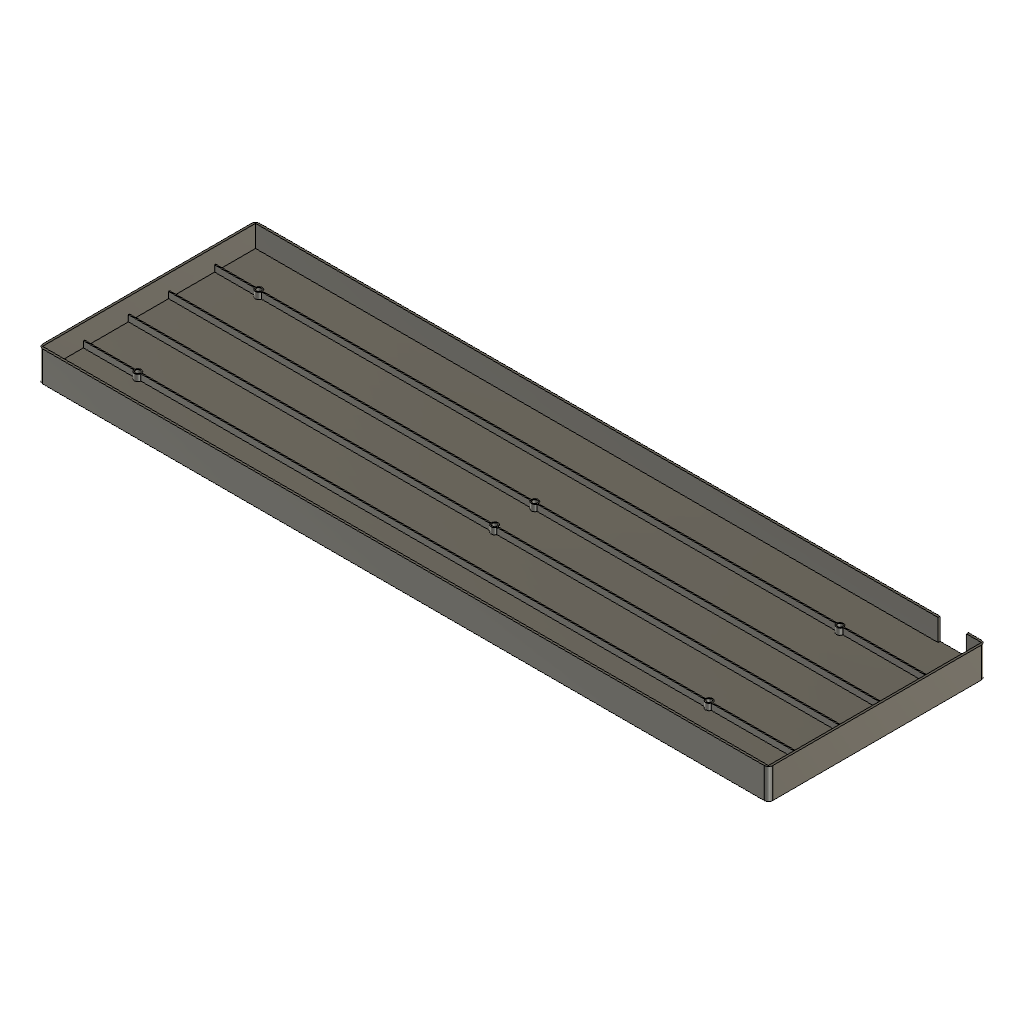
kaze (Autodesk Fusion 360 design; units mm, degrees)
part number: 2026-10-19-18-03-33-046
Autodesk Fusion 360 part; units mm, degrees
sketch "Sketch1" plane through (0, 0, 0) normal (0, 0, 1) x (1, 0, 0)
  line L0 (-60, 25) -> (276, 25)
  line L1 (276, 25) -> (276, -75)
  line L2 (276, -75) -> (-60, -75)
  line L3 (-60, -75) -> (-60, 25)
  dimension "d1" = 336
  dimension "d2" = 100
  constraint horizontal L0
  constraint vertical L1
  constraint horizontal L2
  constraint vertical L3
  measures "d1" distance of L0.start L0.end
  measures "d2" distance of L0.start L2.end
extrude "Extrude1" add sketch "Sketch1" along normal blind 4 makes body 1
sketch "Sketch2" plane through (0, 0, 4) normal (0, 0, 1) x (-1, 0, 0)
  line L0 (60, 75) -> (-276, 75)
  line L1 (-276, 75) -> (-276, -25)
  line L2 (-276, -25) -> (60, -25)
  line L3 (60, -25) -> (60, 75)
  line L4 (60, -25) -> (-276, -25)
  line L5 (-276, -25) -> (-276, 75)
  line L6 (-276, 75) -> (60, 75)
  line L7 (60, 75) -> (60, -25)
  line L8 (59, -24) -> (-275, -24)
  line L9 (-275, -24) -> (-275, 74)
  line L10 (-275, 74) -> (59, 74)
  line L11 (59, 74) -> (59, -24)
  line L12 (-255, -25) -> (-268, -25)
  line L13 (-268, -25) -> (-268, -24)
  line L14 (-268, -24) -> (-255, -24)
  line L15 (-255, -24) -> (-255, -25)
  dimension "d7" = 334
  dimension "d8" = 13
  dimension "d12" = 314
  constraint horizontal L4
  constraint vertical L5
  constraint horizontal L6
  constraint vertical L7
  constraint coincident L0.end L1.start
  constraint coincident L2.end L3.start
  constraint horizontal L8
  constraint vertical L9
  constraint horizontal L10
  constraint vertical L11
  constraint horizontal L12
  constraint vertical L13
  constraint horizontal L14
  constraint vertical L15
  constraint coincident L2 L12.start
  measures "d7" distance of L8.start L8.end
  measures "d8" distance of L12.start L12.end
  measures "d12" distance of L8.start L14.end
extrude "Extrude2" add sketch "Sketch2" along normal blind 10 contours L0 L1 L2 L3 L4 L5 L6 L7 L8 L9 L10 L11 L13 L15 | L2 L4 L8 L12 L13 L14 L15 bodies 1
extrude "Extrude4" cut sketch "Sketch2" along normal blind 10 contours L2 L4 L8 L12 L13 L14 L15 bodies 1
fillet "Fillet1" radius 2 1 edges at (-60, -75, 7) on bodies 1
fillet "Fillet2" radius 2 1 edges at (-60, 25, 7) on bodies 1
fillet "Fillet3" radius 2 1 edges at (276, 25, 7) on bodies 1
fillet "Fillet4" radius 2 1 edges at (276, -75, 7) on bodies 1
sketch "Sketch3" plane through (0, -75, 0) normal (0, -1, 0) x (1, 0, 0)
  line L0 (274, 0) -> (274, 14)
  line L1 (274, 14) -> (-58, 14)
  line L2 (-58, 14) -> (-58, 0)
  line L3 (-58, 0) -> (274, 0)
sketch "Sketch4" plane through (0, 0, 4) normal (0, 0, 1) x (-1, 0, 0)
  circle A0 centre (-109, 15.5) radius 1.1
  line L0 (59, -24) -> (-275, -24)
  circle A1 centre (-109, 34) radius 1.1
  line L1 (-275, 74) -> (59, 74)
  circle A2 centre (-109, 15.5) radius 1.6
  circle A3 centre (-109, 34) radius 1.6
  line L2 (59.0194, 15.5) -> (-275, 15.5)
  line L3 (-275, 15.5) -> (-275, 16)
  line L4 (-275, 16) -> (59.0194, 16)
  line L5 (59.0194, 16) -> (59.0194, 15.5)
  line L6 (59, 34) -> (-275.0529, 34)
  line L7 (-275.0529, 34) -> (-275.0529, 34.5)
  line L8 (-275.0529, 34.5) -> (59, 34.5)
  line L9 (59, 34.5) -> (59, 34)
  line L10 (58.9744, -5.185) -> (-275.1602, -5.185)
  line L11 (-275.1602, -5.185) -> (-275.1602, -5.685)
  line L12 (-275.1602, -5.685) -> (58.9744, -5.685)
  line L13 (58.9744, -5.685) -> (58.9744, -5.185)
  line L14 (58.9744, 54.7169) -> (-274.9204, 54.7169)
  line L15 (-274.9204, 54.7169) -> (-274.9204, 55.2169)
  line L16 (-274.9204, 55.2169) -> (58.9744, 55.2169)
  line L17 (58.9744, 55.2169) -> (58.9744, 54.7169)
  line L18 (59, 74) -> (59, -24)
  circle A4 centre (39, -5.5) radius 1.1
  line L19 (60, 75) -> (60, -25)
  line L20 (60, -25) -> (-276, -25)
  circle A5 centre (34.15, 55) radius 1.1
  line L21 (-276, 75) -> (60, 75)
  circle A6 centre (-228.5, -5.4) radius 1.1
  line L22 (-276, -25) -> (-276, 75)
  circle A7 centre (-228.4, 54.7) radius 1.1
  circle A8 centre (39, -5.5) radius 1.6
  circle A9 centre (34.15, 55) radius 1.6
  circle A10 centre (-228.5, -5.4) radius 1.6
  line L23 (-275, -24) -> (-275, 74)
  circle A11 centre (-228.4, 54.7) radius 1.6
  dimension "d23" = 2.2
  dimension "d24" = 39.5
  dimension "d25" = 2.2
  dimension "d26" = 40
  dimension "d27" = 3.2
  dimension "d28" = 3.2
  dimension "d39" = 0.5
  dimension "d40" = 0.5
  dimension "d41" = 0.5
  dimension "d54" = 168
  dimension "d55" = 168
  dimension "d60" = 2.2
  dimension "d63" = 2.2
  dimension "d66" = 2.2
  dimension "d68" = 47.5
  dimension "d69" = 2.2
  dimension "d70" = 20
  dimension "d71" = 18.5
  dimension "d72" = 19
  dimension "d73" = 24.85
  dimension "d74" = 3.2
  dimension "d75" = 3.2
  dimension "d76" = 18.6
  dimension "d77" = 3.2
  dimension "d78" = 46.6
  dimension "d79" = 19.3
  dimension "d80" = 3.2
  constraint horizontal L2
  constraint vertical L3
  constraint horizontal L4
  constraint vertical L5
  constraint horizontal L6
  constraint vertical L7
  constraint horizontal L8
  constraint vertical L9
  constraint horizontal L10
  constraint vertical L11
  constraint horizontal L12
  constraint vertical L13
  constraint horizontal L14
  constraint vertical L15
  constraint horizontal L16
  constraint vertical L17
  constraint concentric A4 A8
  constraint concentric A5 A9
  constraint concentric A6 A10
  constraint concentric A7 A11
  measures "d23" diameter of A0
  measures "d24" distance of A0.centre L0
  measures "d25" diameter of A1
  measures "d26" distance of A1.centre L1
  measures "d27" diameter of A2
  measures "d28" diameter of A3
  measures "d39" distance of L6.start L8.end
  measures "d40" distance of L10.start L12.end
  measures "d41" distance of L14.start L16.end
  measures "d54" distance of A0.centre L18
  measures "d55" distance of A1.centre L18
  measures "d60" diameter of A4
  measures "d63" diameter of A5
  measures "d66" diameter of A6
  measures "d68" distance of A6.centre L22
  measures "d69" diameter of A7
  measures "d70" distance of L18 A4.centre
  measures "d71" distance of L0 A4.centre
  measures "d72" distance of L1 A5.centre
  measures "d73" distance of L18 A5.centre
  measures "d74" diameter of A8
  measures "d75" diameter of A9
  measures "d76" distance of L0 A6.centre
  measures "d77" diameter of A10
  measures "d78" distance of A7.centre L23
  measures "d79" distance of L1 A7.centre
  measures "d80" diameter of A11
extrude "Extrude5" add sketch "Sketch4" along normal blind 2.9 contours A0 A2 L2 | A0 A2 L2 L4 | A0 A2 L4 | A0 A2 L2 L4 bodies 1
extrude "Extrude6" add sketch "Sketch4" along normal blind 2.9 contours A1 A3 L6 L8 | A1 A3 L6 | A1 A3 L6 L8 | A1 A3 L8 bodies 1
extrude "Extrude7" add sketch "Sketch4" along normal blind 2.9 contours A2 L2 L3 L4 L23 bodies 1
extrude "Extrude11" add sketch "Sketch4" along normal blind 2.9 contours A3 L6 L8 L23 | L6 L7 L8 L23 bodies 1
extrude "Extrude16" add sketch "Sketch4" along normal blind 2.9 contours A2 L2 L4 L18 bodies 1
extrude "Extrude17" add sketch "Sketch4" along normal blind 2.9 contours A3 L6 L8 L9 L18 bodies 1
extrude "Extrude18" add sketch "Sketch4" along normal blind 2.9 contours L12 A4 A8 bodies 1
extrude "Extrude19" add sketch "Sketch4" along normal blind 2.9 contours L10 A4 A8 bodies 1
extrude "Extrude20" add sketch "Sketch4" along normal blind 2.9 separate body contours L10 L12 A8 A10 makes body 2
extrude "Extrude21" add sketch "Sketch4" along normal blind 2.9 separate body contours L10 L12 L13 A8 makes body 3
extrude "Extrude22" add sketch "Sketch4" along normal blind 2.9 contours L10 L12 A4 A8 picked at (37.5708, -5.5875) bodies 1 2
extrude "Extrude23" add sketch "Sketch4" along normal blind 2.9 contours L10 L12 A4 A8 picked at (40.2535, -5.3237) bodies 1 3
extrude "Extrude24" add sketch "Sketch4" along normal blind 2.9 contours L10 L12 A6 A10 picked at (-227.2441, -5.5592) bodies 1
extrude "Extrude25" add sketch "Sketch4" along normal blind 2.9 contours L10 L12 A6 A10 picked at (-229.927, -5.2822) bodies 1
extrude "Extrude26" add sketch "Sketch4" along normal blind 2.9 contours L12 A6 A10 bodies 1
extrude "Extrude27" add sketch "Sketch4" along normal blind 2.9 contours L10 A6 A10 bodies 1
extrude "Extrude28" add sketch "Sketch4" along normal blind 2.9 contours L10 L12 A10 L23 bodies 1
extrude "Extrude29" add sketch "Sketch4" along normal blind 2.9 contours L14 L15 L16 A11 bodies 1
extrude "Extrude30" add sketch "Sketch4" along normal blind 2.9 contours L14 L16 A7 A11 picked at (-229.7799, 55.0817) bodies 1
extrude "Extrude31" add sketch "Sketch4" along normal blind 2.9 contours L14 L16 A7 A11 picked at (-227.0201, 55.0817) bodies 1
extrude "Extrude32" add sketch "Sketch4" along normal blind 2.9 contours L14 A7 A11 bodies 1
extrude "Extrude33" add sketch "Sketch4" along normal blind 2.9 contours L16 A7 A11 bodies 1
extrude "Extrude34" add sketch "Sketch4" along normal blind 2.9 contours L14 L16 A9 A11 bodies 1
extrude "Extrude35" add sketch "Sketch4" along normal blind 2.9 contours L14 L16 A5 A9 picked at (32.7231, 55.1197) bodies 1
extrude "Extrude36" add sketch "Sketch4" along normal blind 2.9 contours L14 L16 A5 A9 picked at (35.406, 54.8418) bodies 1
extrude "Extrude37" add sketch "Sketch4" along normal blind 2.9 contours L14 A5 A9 bodies 1
extrude "Extrude38" add sketch "Sketch4" along normal blind 2.9 contours L16 A5 A9 bodies 1
extrude "Extrude39" add sketch "Sketch4" along normal blind 2.9 contours L14 L16 L17 A9 bodies 1
